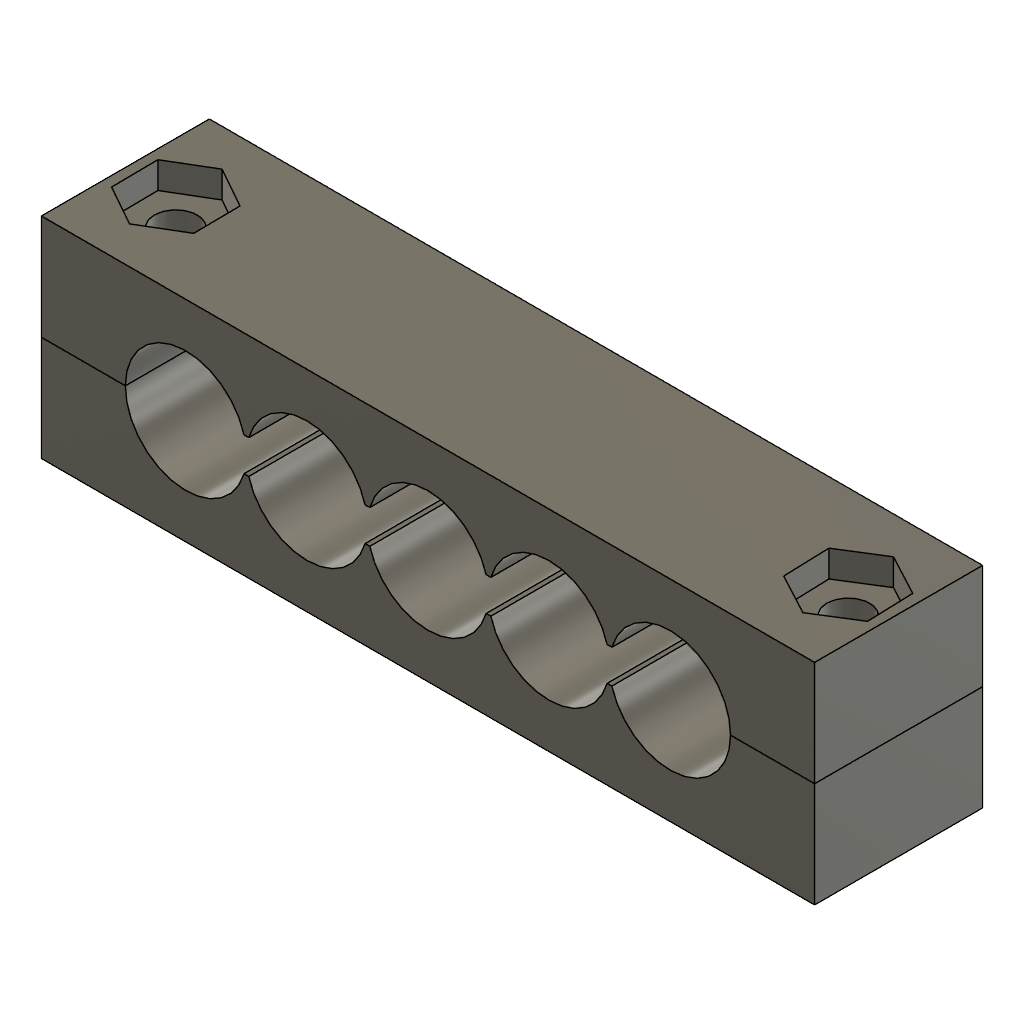
AA Parametric (Autodesk Fusion 360 design; units mm, degrees)
Autodesk Fusion 360 part; units mm, degrees
sketch "Sketch1" plane through (0, 0, 0) normal (0, 0, 1) x (1, 0, 0)
  line L0 (0, 0) -> (92, 0)
  line L1 (92, 0) -> (92, 25)
  line L2 (92, 25) -> (0, 25)
  line L3 (0, 25) -> (0, 0)
  dimension "d1" = 92
  dimension "d2" = 25
  constraint horizontal L0
  constraint vertical L1
  constraint horizontal L2
  constraint vertical L3
  constraint coincident L0.start L3.end
  measures "d1" distance of L0.start L0.end
  measures "d2" distance of L0.start L2.end
extrude "Extrude1" add sketch "Sketch1" along normal blind 20 makes body 1
sketch "Sketch2" plane through (0, 0, 20) normal (0, 0, 1) x (1, 0, 0)
  line L0 (0, 25) -> (0, 0)
  line L1 (0, 0) -> (92, 0)
  line L2 (92, 0) -> (92, 25)
  line L3 (92, 25) -> (0, 25)
  line L4 (92, 12.5) -> (0, 12.5) construction
  circle A0 centre (17.2, 12.5) radius 7.2
  circle A1 centre (31.6, 12.5) radius 7.2
  circle A2 centre (46, 12.5) radius 7.2
  circle A3 centre (60.4, 12.5) radius 7.2
  circle A4 centre (74.8, 12.5) radius 7.2
  dimension "d37" = 14.4
  dimension "d38" = 17.2
  dimension "d43" = 14.4
  dimension "d44" = 0
  constraint midpoint L2 L4.start
  constraint midpoint L0 L4.end
  constraint coincident L4 A0.centre
  measures "d37" diameter of A0
  measures "d38" horizontal distance of L0.end A0.centre
extrude "Extrude2" cut sketch "Sketch2" against normal through all contours A0 bodies 1
pattern_linear "R-Pattern1" count 5 spacing 14.4 along (1, 0, 0) of "Extrude2"
sketch "Sketch3" plane through (0, 0, 20) normal (0, 0, 1) x (1, 0, 0)
  line L0 (0, 25) -> (0, 0)
  line L1 (0, 0) -> (92, 0)
  line L2 (92, 0) -> (92, 25)
  line L3 (92, 25) -> (0, 25)
  line L4 (17.2621, 14.499) -> (74.8, 14.5)
  line L5 (17.2571, 10.5008) -> (74.7755, 10.5001)
  arc A0 (74.7755, 10.5001) -> (74.8, 14.5) centre (74.8, 12.5) ccw
  circle A1 centre (17.2, 12.5) radius 7.2
  arc A2 (17.2621, 14.499) -> (17.2571, 10.5008) centre (17.2, 12.5) ccw
  arc A3 (53.2, 12.5) -> (38.8, 12.5) centre (46, 12.5) ccw
  arc A4 (38.8, 12.5) -> (24.4, 12.5) centre (31.6, 12.5) ccw
  arc A5 (67.6, 12.5) -> (53.2, 12.5) centre (60.4, 12.5) ccw
  circle A6 centre (74.8, 12.5) radius 7.2
  arc A7 (53.2, 12.5) -> (67.6, 12.5) centre (60.4, 12.5) ccw
  arc A8 (38.8, 12.5) -> (53.2, 12.5) centre (46, 12.5) ccw
  arc A9 (24.4, 12.5) -> (38.8, 12.5) centre (31.6, 12.5) ccw
  dimension "d17" = 4
  dimension "d39" = 4
  dimension "d45" = 57.6
  dimension "d46" = 12.5
  constraint tangent L4 A0
  constraint concentric A1 A2
  measures "d17" diameter of A0
  measures "d39" diameter of A2
  measures "d45" distance of A0.centre A1.centre
  measures "d46" distance of L3 A0.centre
extrude "Extrude3" cut sketch "Sketch3" against normal through all contours L4 L5 A1 A2 | L4 A1 A4 | L4 L5 A4 A9 | L5 A1 A9 | L4 A3 A4 | L4 L5 A3 A8 | L5 A8 A9 | L4 A3 A5 | L4 L5 A5 A7 | L5 A7 A8 | L4 A5 A6 | L4 L5 A0 A6 | L5 A6 A7 picked at (19.6397, 12.4999) picked at (72.3918, 12.5) bodies 1
sketch "Sketch4" plane through (0, 0, 0) normal (0, -1, 0) x (1, 0, 0)
  line L0 (0, 0) -> (92, 0)
  line L1 (92, 0) -> (92, 20)
  line L2 (92, 20) -> (0, 20)
  line L3 (0, 20) -> (0, 0)
  line L4 (0, 10) -> (92, 10) construction
  point P0 (6, 10)
  point P1 (86, 10)
  dimension "d24" = 6
  dimension "d25" = 6
  constraint midpoint L3 L4.start
  constraint midpoint L1 L4.end
  constraint coincident L4 P0
  constraint coincident L4 P1
  measures "d24" distance of L3 P0
  measures "d25" distance of L1 P1
hole "Hole1" at (6, 0, 10) at (86, 0, 10) direction (0, 1, 0) diameter 5.105 depth 25 tip angle 180 counterbore diameter 9.525 counterbore depth 4.826 bodies 1
sketch "Sketch5" plane through (0, 25, 0) normal (0, 1, 0) x (-1, 0, 0)
  circle A0 centre (-6, 10) radius 2.5525
  circle A1 centre (-86, 10) radius 2.5525
  line L0 (-92, 0) -> (0, 0)
  line L1 (0, 0) -> (0, 20)
  line L2 (0, 20) -> (-92, 20)
  line L3 (-92, 20) -> (-92, 0)
  line L4 (-1.1415, 7.2707) -> (-1.2071, 12.8429)
  line L5 (-1.2071, 12.8429) -> (-6.0656, 15.5722)
  line L6 (-6.0656, 15.5722) -> (-10.8585, 12.7293)
  line L7 (-10.8585, 12.7293) -> (-10.7929, 7.1571)
  line L8 (-10.7929, 7.1571) -> (-5.9344, 4.4278)
  line L9 (-5.9344, 4.4278) -> (-1.1415, 7.2707)
  line L10 (-90.7311, 7.0555) -> (-85.8155, 4.4305)
  line L11 (-85.8155, 4.4305) -> (-81.0844, 7.375)
  line L12 (-81.0844, 7.375) -> (-81.2689, 12.9445)
  line L13 (-81.2689, 12.9445) -> (-86.1845, 15.5695)
  line L14 (-86.1845, 15.5695) -> (-90.9156, 12.625)
  line L15 (-90.9156, 12.625) -> (-90.7311, 7.0555)
  point P0 (-6, 10)
  point P1 (-86, 10)
  dimension "d32" = 4.826
  dimension "d33" = 4.826
  constraint coincident P0 A0.centre
  constraint coincident P1 A1.centre
  measures "d32" distance of P0 L9
  measures "d33" distance of P1 L15
extrude "Extrude4" cut sketch "Sketch5" against normal blind 3.175 contours L4 L5 L6 L7 L8 L9 | L10 L11 L12 L13 L14 L15 bodies 1
sketch "Sketch6" plane through (0, 0, 0) normal (0, 0, -1) x (-1, 0, 0)
  line L0 (0, 0) -> (0, 25)
  line L1 (0, 25) -> (-92, 25)
  line L2 (-92, 25) -> (-92, 0)
  line L3 (-92, 0) -> (0, 0)
  line L4 (-92, 12.5) -> (0, 12.5)
  arc A0 (-24.1169, 10.5007) -> (-24.1169, 14.4991) centre (-17.2, 12.5) ccw
  line L5 (-39.0832, 14.4994) -> (-38.5168, 14.4994)
  line L6 (-38.5168, 10.5006) -> (-39.0832, 10.5006)
  line L7 (-24.1169, 10.5007) -> (-24.6831, 10.5007)
  arc A1 (-24.6831, 14.4992) -> (-38.5168, 14.4994) centre (-31.6, 12.5) ccw
  line L8 (-24.6831, 14.4992) -> (-24.1169, 14.4991)
  arc A2 (-38.5168, 10.5006) -> (-24.6831, 10.5007) centre (-31.6, 12.5) ccw
  arc A3 (-52.9168, 10.5004) -> (-39.0832, 10.5006) centre (-46, 12.5) ccw
  line L9 (-52.9168, 10.5004) -> (-53.4832, 10.5004)
  arc A4 (-67.3167, 10.5002) -> (-53.4832, 10.5004) centre (-60.4, 12.5) ccw
  line L10 (-53.4833, 14.4996) -> (-52.9168, 14.4996)
  arc A5 (-39.0832, 14.4994) -> (-52.9168, 14.4996) centre (-46, 12.5) ccw
  line L11 (-67.3167, 10.5002) -> (-67.8833, 10.5002)
  arc A6 (-67.8833, 14.4999) -> (-67.8833, 10.5002) centre (-74.8, 12.5) ccw
  line L12 (-67.8833, 14.4999) -> (-67.3167, 14.4999)
  arc A7 (-53.4833, 14.4996) -> (-67.3167, 14.4999) centre (-60.4, 12.5) ccw
  constraint midpoint L2 L4.start
  constraint midpoint L0 L4.end
split "Split1" by curves path "Sketch6" along L4 bodies 1 makes body 2 at (58.4391, 0, 17.9783)
equation "d1 = Length"
equation "d2 = Width"
equation "d3 = Height"
equation "d9 = CellDia"
equation "Width = 25 mm"
equation "Length = Num_Cells * CellDia + 20 mm"
equation "Height = 20 mm"
equation "CellDia = 14.4 mm" comment "AAA 10.00 + 0.2  dia, AA 14.5 + 0.2"
equation "d16 = SegmentWidth"
equation "d17 = d16"
equation "SegmentWidth = 4 mm"
equation "d21 = CellDia"
equation "d24 = ScrewSpace"
equation "d25 = d24"
equation "d26 = Width"
equation "ScrewSpace = 6 mm"
equation "d37 = d9"
equation "d38 = ( Length - ( Num_Cells - 1 ) * CellDia ) / 2"
equation "d39 = d17"
equation "Num_Cells = 5"
equation "d41 = Num_Cells"
equation "d43 = CellDia"
equation "d45 = ( Num_Cells - 1 ) * CellDia"
equation "d48 = Num_Cells"
equation "d50 = CellDia"
